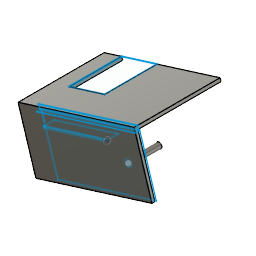
BaseWall_Left (Autodesk Fusion 360 design; units mm, degrees)
Autodesk Fusion 360 part; units mm, degrees
sketch "sketch 1168" plane through (0, 0, 21.5) normal (0, 0, 1) x (1, 0, 0)
  circle A0 centre (160, 50) radius 4.75
extrude "돌출1" add sketch "sketch 1168" along normal blind 10 and the other way blind 50
sketch "sketch 1181" plane through (0, 0, 21.5) normal (0, 0, 1) x (1, 0, 0)
  line L0 (18.9922, 55.4771) -> (153.1211, 97.3924)
  line L1 (18.9922, 55.4771) -> (23.4663, 41.1599)
  line L2 (23.4663, 41.1599) -> (45.764, -30.1928)
  line L3 (205.3614, 19.6814) -> (45.764, -30.1928)
  line L4 (178.5895, 105.3513) -> (205.3614, 19.6814)
  line L5 (153.1211, 97.3924) -> (178.5895, 105.3513)
extrude "돌출2" add sketch "sketch 1181" along normal blind 5 from surface at 2
extrude "돌출3" cut 1 faces at (158.7554, 47.6342, 31.5) along direction (0, 0, -1) blind 3
sketch "sketch 1210" plane through (-14.1045, 45.1344, 0) normal (-0.298275, 0.95448, 0) x (0, 0, 1)
  line L0 (28.5, 201.8838) -> (23.5, 201.8838)
  line L1 (23.5, 201.8838) -> (23.5, 34.6751)
  line L2 (23.5, 34.6751) -> (28.5, 34.6751)
  line L3 (28.5, 34.6751) -> (28.5, 201.8838)
extrude "돌출4" add sketch "sketch 1210" along normal blind 7
sketch "sketch 1231" plane through (0, 0, 23.5) normal (0, 0, -1) x (-1, 0, 0)
  line L0 (-176.5016, 112.0326) -> (-177.993, 107.2602)
  line L1 (-176.5016, 112.0326) -> (-177.993, 107.2602)
  line L2 (-177.993, 107.2602) -> (-18.3956, 57.386)
  line L3 (-18.3956, 57.386) -> (-16.9043, 62.1584)
  line L4 (-18.3956, 57.386) -> (-16.9043, 62.1584)
  line L5 (-176.5016, 112.0326) -> (-16.9043, 62.1584)
  line L6 (-176.5016, 112.0326) -> (-16.9043, 62.1584)
extrude "돌출5" add sketch "sketch 1231" along normal blind 14.5
extrude "돌출6" add 1 faces at (71.0976, 75.6016, 9) along direction (0, 0, -1) blind 120
sketch "sketch 1255" plane through (0, 0, 23.5) normal (0, 0, -1) x (-1, 0, 0)
  spline S0 degree 5 poles (-128.5871, 68.0359) (-128.549, 67.9783) (-128.4737, 67.8627) (-128.3635, 67.6882) (-128.2218, 67.4533) (-128.0542, 67.1557) (-127.897, 66.8537) (-127.7511, 66.5471) (-127.6168, 66.2355) (-127.4938, 65.9193) (-127.3812, 65.5987) (-127.2987, 65.3391) (-127.2409, 65.1427) (-127.2041, 65.011) (-127.1862, 64.945) knots 0 0 0 0 0 0 0.1 0.2 0.3 0.4 0.5 0.6 0.7 0.8 0.9 1 1 1 1 1 1
  line L0 (-127.1862, 64.945) -> (-25.9225, 33.3001)
  line L1 (-25.9225, 33.3001) -> (-25.1672, 35.7172)
  line L2 (-25.9225, 33.3001) -> (-25.1672, 35.7172)
  line L3 (-128.5871, 68.0359) -> (-25.1672, 35.7172)
extrude "돌출7" add sketch "sketch 1255" along normal blind 17
sketch "스케치1" plane through (-7.9295, 25.3745, 0) normal (-0.298275, 0.95448, 0) x (0, 0, 1)
  line L0 (23.5, 34.6751) -> (23.5, 143.0272)
  line L1 (23.5, 143.0272) -> (6.5, 143.0272)
  line L2 (6.5, 143.0272) -> (6.5, 34.6751)
  line L3 (6.5, 34.6751) -> (23.5, 34.6751)
  line L4 (6.5, 34.6751) -> (9, 34.6751)
  line L5 (9, 34.6751) -> (9, 143.0272)
  line L6 (9, 143.0272) -> (6.5, 143.0272)
  constraint coincident L2.end L3.start
  constraint coincident L3 L4.end
  constraint coincident L1 L5.end
  constraint perpendicular L1 L5
  constraint coincident L1.end L2.start
extrude "돌출8" add sketch "스케치1" along normal blind 10 contours L1 L2 L3 L4 L5 L6
sketch "스케치2" plane through (33.0967, 10.3427, 0) normal (-0.95448, -0.298275, 0) x (0, 0, 1)
  line L0 (23.5, 24.0522) -> (23.5, -42.4687)
  line L1 (23.5, -42.4687) -> (28.5, -42.4687)
  line L2 (28.5, -42.4687) -> (28.5, 54.2869)
  line L3 (28.5, 54.2869) -> (-111, 54.2869)
  line L4 (-111, 54.2869) -> (-111, 49.2869)
  line L5 (-111, 49.2869) -> (23.5, 49.2869)
  line L6 (23.5, 49.2869) -> (23.5, 26.5846)
  line L7 (23.5, 26.5846) -> (9, 26.5846)
  line L8 (9, 26.5846) -> (9, 36.5846)
  line L9 (9, 36.5846) -> (6.5, 36.5846)
  line L10 (6.5, 36.5846) -> (6.5, 24.0522)
  line L11 (6.5, 24.0522) -> (23.5, 24.0522)
  line L12 (21.5, 32.2869) -> (21.5, 47.2869)
  line L13 (21.5, 47.2869) -> (-111, 47.2869)
  line L14 (-111, 47.2869) -> (-111, 42.2869)
  line L15 (-111, 42.2869) -> (11, 42.2869)
  line L16 (11, 42.2869) -> (11, 32.2869)
  line L17 (11, 32.2869) -> (21.5, 32.2869)
sketch "sketch 1301" plane through (-16.1924, 51.8157, 0) normal (-0.298275, 0.95448, 0) x (0, 0, 1)
  line L0 (-111, 94.6751) -> (-111, 34.6751)
  line L1 (-111, 94.6751) -> (-111, 34.6751)
  line L2 (-111, 34.6751) -> (-26, 34.6751)
  line L3 (-111, 34.6751) -> (-26, 34.6751)
  line L4 (-26, 34.6751) -> (-26, 94.6751)
  line L5 (-26, 94.6751) -> (-111, 94.6751)
extrude "돌출9" cut sketch "sketch 1301" against normal blind 5
extrude "돌출10" add sketch "스케치2" along normal blind 30 contours L0 L1 L2 L3 L4 L5 L6 L7 L8 L9 L10 L11
